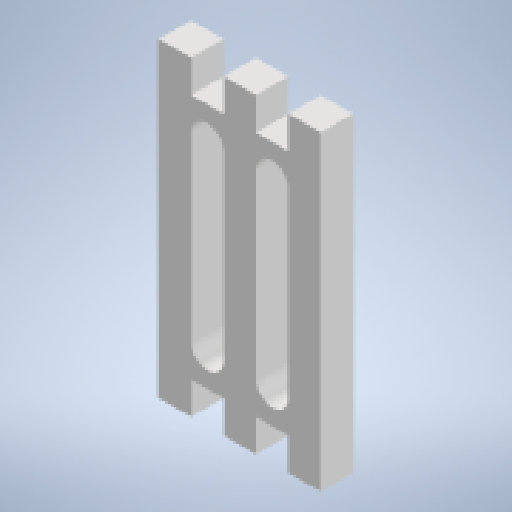
# Autodesk Inventor part: KneeFrontL
Saved by Autodesk Inventor 2025.2 (Build 292293000, 293)
## iProperties
Created: 2025-06-23
Part Number: KneeFrontL
Material: Generic
Document SubType Name: Modeling
Designer: ricoa
Density: 1 g/cm^3
Appearance: Default
Author: ricoa
Autodesk Inventor part; units mm, degrees
ref_plane "YZ Plane" through (0, 0, 0) normal (1, 0, 0) x (0, 1, 0)
ref_plane "XZ Plane" through (0, 0, 0) normal (0, 1, 0) x (-1, 0, 0)
ref_plane "XY Plane" through (0, 0, 0) normal (0, 0, 1) x (1, 0, 0)
sketch "Sketch1" plane through (0, 0, 0) normal (0, 0, 1) x (1, 0, 0)
  line L0 (-10, 0) -> (-5, 0) projected
  line L1 (-5, 0) -> (-5, 5) projected
  line L2 (0, 0) -> (5, 0) projected
  line L3 (10, 0) -> (15, 0) projected
  line L4 (15, 0) -> (15, 5) projected
  line L5 (-10, 48) -> (-5, 48) projected
  line L6 (0, 48) -> (5, 48) projected
  line L7 (10, 48) -> (15, 48) projected
  line L8 (-10, 0) -> (-10, 48)
  line L9 (10, 0) -> (10, 5)
  line L10 (10, 5) -> (5, 5)
  line L11 (5, 5) -> (5, 0)
  line L12 (0, 0) -> (0, 5)
  line L13 (0, 5) -> (-5, 5)
  line L14 (-5, 48) -> (-5, 43)
  line L15 (-5, 43) -> (0, 43)
  line L16 (0, 43) -> (0, 48)
  line L17 (5, 48) -> (5, 43)
  line L18 (5, 43) -> (10, 43)
  line L19 (10, 48) -> (10, 43)
  line L20 (15, 5) -> (20, 5)
  line L21 (20, 5) -> (20, 43)
  line L22 (15, 48) -> (15, 43)
  line L23 (15, 5) -> (15, 0)
  line L24 (18.75, 43) -> (18.75, 48) projected
  line L25 (18.75, 5) -> (18.75, 43)
  line L26 (15, 5) -> (15, 43)
  dimension "d0" = 5
  dimension "d1" = 5
  dimension "d4" = 5
  constraints: 36 end point, 7 point on line, 6 perpendicular, 1 collinear, 1 horizontal, 1 parallel, 1 vertical
  measures "d0" distance of L3.start L9.end
  measures "d1" distance of L5.end L14.end
  measures "d4" distance of L4.end L20.end
extrude "Extrusion1" add sketch "Sketch1" along normal blind 5
sketch "Sketch2" plane through (0, 0, 5) normal (0, 0, 1) x (1, 0, 0)
  line L0 (-5, 5) -> (0, 5) projected
  line L1 (-2.5, 5) -> (-2.5, 10)
  line L2 (0, 43) -> (-5, 43) projected
  line L3 (-2.5, 43) -> (-2.5, 38)
  line L4 (-2.5, 10) -> (-2.5, 38) construction
  line L5 (0, 10) -> (0, 38)
  line L6 (-5, 38) -> (-5, 10)
  arc A0 (-5, 10) -> (0, 10) centre (-2.5, 10) ccw
  arc A1 (0, 38) -> (-5, 38) centre (-2.5, 38) ccw
  line L7 (7.5, 10) -> (7.5, 38) construction
  line L8 (10, 10) -> (10, 38)
  line L9 (5, 38) -> (5, 10)
  arc A2 (5, 10) -> (10, 10) centre (7.5, 10) ccw
  arc A3 (10, 38) -> (5, 38) centre (7.5, 38) ccw
  point P0 (0, 0)
  point P1 (-2.5, 24)
  point P2 (7.5, 24)
  dimension "d5" = 5
  dimension "d6" = 5
  dimension "d7" = 5
  constraints: 20 end point, 8 point on circle, 8 tangent, 4 centre point, 4 midpoint, 3 parallel, 2 vertical, 1 collinear
  measures "d5" distance of L1.start L1.end
  measures "d6" distance of L3.start L3.end
  measures "d7" diameter of A3
extrude "Extrusion2" cut sketch "Sketch2" against normal blind 5
body "Solid1"
